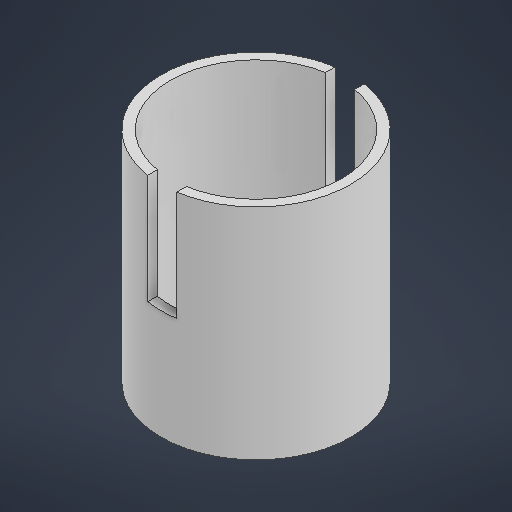
# Autodesk Inventor part: Motor Coupler_1
Saved by Autodesk Inventor 2027 (Build 310192060, 192F)
## iProperties
Created: 2026-08-03
Part Number: Motor Coupler_1
Material: Generic
Document SubType Name: Modeling
Designer: troop
Density: 1 g/cm^3
Appearance: Default
Author: troop
Autodesk Inventor part; units mm, degrees
ref_plane "YZ Plane" through (0, 0, 0) normal (1, 0, 0) x (0, 1, 0)
ref_plane "XZ Plane" through (0, 0, 0) normal (0, 1, 0) x (-1, 0, 0)
ref_plane "XY Plane" through (0, 0, 0) normal (0, 0, 1) x (1, 0, 0)
sketch "Sketch1" plane through (0, 0, 0) normal (0, 1, 0) x (-1, 0, 0)
  circle A0 centre (0, 0) radius 14.85
  circle A1 centre (0, 0) radius 16.5
  dimension "d0" = 29.7
  dimension "d1" = 33
  constraints: 2 centre point, 2 coincident
  measures "d0" diameter of A0
  measures "d1" diameter of A1
extrude "Extrusion1" add sketch "Sketch1" along normal blind 38.1
sketch "Sketch2" plane through (0, 0, 0) normal (0, 0, 1) x (1, 0, 0)
  line L0 (16.5, 38.1) -> (-16.5, 38.1) projected
  line L1 (-2.54, 38.1) -> (2.54, 38.1)
  line L2 (2.54, 38.1) -> (2.54, 19.05)
  line L3 (2.54, 19.05) -> (-2.54, 19.05)
  line L4 (-2.54, 19.05) -> (-2.54, 38.1)
  point P0 (0, 0)
  point P1 (0, 38.1)
  dimension "d4" = 19.05
  dimension "d5" = 5.08
  dimension "d6" = 2.54
  constraints: 8 end point, 2 parallel, 1 horizontal, 1 midpoint, 1 perpendicular, 1 point on line
  measures "d4" distance of L1.end L2.end
  measures "d5" distance of L2.end L3.end
  measures "d6" distance from line of point (0, 38.1) L2
extrude "Extrusion2" cut sketch "Sketch2" along normal mid plane 38.1
body "Solid1"
